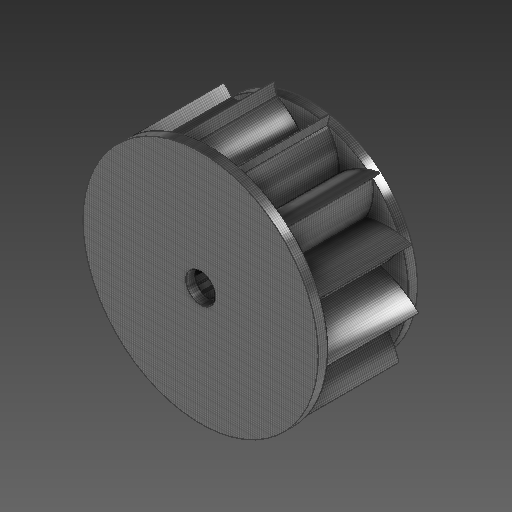
# Autodesk Inventor part: Turbine
Saved by Autodesk Inventor 2026.1 (Build 301233020, 233B)
## iProperties
Created: 2026-10-21
Part Number: Turbine
Material: Generic
Document SubType Name: Modeling
Designer: YmCris
Density: 1 g/cm^3
Appearance: Default
Author: YmCris
Autodesk Inventor part; units mm, degrees
ref_plane "YZ Plane" through (0, 0, 0) normal (1, 0, 0) x (0, 1, 0)
ref_plane "XZ Plane" through (0, 0, 0) normal (0, 1, 0) x (-1, 0, 0)
sketch "Sketch1" plane through (0, 0, 0) normal (0, 0, 1) x (1, 0, 0)
  circle A0 centre (0, 0) radius 16
  circle A1 centre (0, 0) radius 127.5
  dimension "d0" = 32
  dimension "d1" = 255
  constraints: 2 centre point, 2 coincident
  measures "d0" diameter of A0
  measures "d1" diameter of A1
extrude "Extrusion1" add sketch "Sketch1" along normal blind 10
ref_plane "Work Plane1" through (0, 0, -100) normal (0, 0, -1) x (-1, 0, 0)
sketch "Sketch2" plane through (0, 0, -100) normal (0, 0, -1) x (-1, 0, 0)
  circle A0 centre (0, 0) radius 22.5
  circle A1 centre (0, 0) radius 115
  dimension "d5" = 45
  dimension "d6" = 230
  constraints: 2 centre point, 2 coincident
  measures "d5" diameter of A0
  measures "d6" diameter of A1
extrude "Extrusion2" add sketch "Sketch2" along normal blind 10
sketch "Sketch3" plane through (0, 0, 0) normal (0, 0, -1) x (-1, 0, 0)
  circle A0 centre (0, 0) radius 16 projected
  circle A1 centre (0, 0) radius 127.5 projected
  arc A2 (0, -16) -> (0, -127.5) centre (72.0298, -71.75) ccw
  line L0 (0, -16) -> (0, -127.5)
  constraints: 2 end point, 2 point on circle, 2 vertical alignment, 1 centre point, 1 vertical, 2 other
sketch "Sketch4" plane through (0, 0, -100) normal (0, 0, 1) x (1, 0, 0)
  circle A0 centre (0, 0) radius 22.5 projected
  circle A1 centre (0, 0) radius 115 projected
  arc A2 (0, -22.5) -> (0, -115) centre (36.2382, -68.75) ccw
  line L0 (0, -115) -> (0, -22.5)
  constraints: 2 end point, 2 point on circle, 2 vertical alignment, 1 centre point, 1 vertical, 2 other
extrude "Extrusion3" add sketch "Sketch3" along normal blind 100 contours L0 A2
extrude "Extrusion4" add sketch "Sketch4" along normal blind 100 contours L0 A2
pattern_circular "Circular Pattern1" count 13 over 360 about axis through (0, 0, -10) along (0, 0, 1) of "Extrusion4", "Extrusion3"
body "Solid1"
